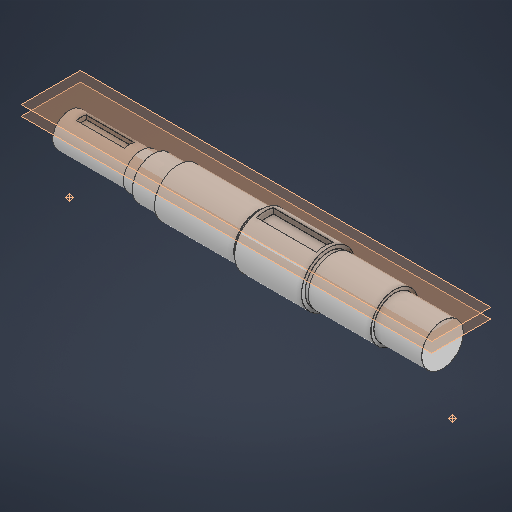
# Autodesk Inventor part: 1
Saved by Autodesk Inventor 2026 (Build 300175000, 175)
## iProperties
Created: 2026-08-23
Part Number: 1
Material: 常规
Document SubType Name: Modeling
Designer: 14170
Density: 1 g/cm^3
Appearance: 默认
Author: 14170
Autodesk Inventor part; units mm, degrees
ref_plane "YZ Plane" through (0, 0, 0) normal (1, 0, 0) x (0, 1, 0)
ref_plane "XY Plane" through (0, 0, 0) normal (0, 0, 1) x (1, 0, 0)
sketch "草图2" plane through (0, 0, 0) normal (0, 1, 0) x (1, 0, 0)
  line L0 (0, 0) -> (312, 0)
  line L1 (312, 0) -> (312, 17.5)
  line L2 (312, 17.5) -> (272, 17.5)
  line L3 (272, 17.5) -> (272, 20)
  line L4 (272, 20) -> (216.5, 20)
  line L5 (216.5, 20) -> (216.5, 22.5)
  line L6 (216.5, 22.5) -> (160.5, 22.5)
  line L7 (160.5, 22.5) -> (160.5, 20)
  line L8 (160.5, 20) -> (91, 20)
  line L9 (91, 20) -> (91, 17.5)
  line L10 (91, 17.5) -> (70, 17.5)
  line L11 (70, 17.5) -> (70, 15)
  line L12 (70, 15) -> (60, 15)
  line L13 (60, 15) -> (60, 14)
  line L14 (60, 14) -> (0, 14)
  line L15 (0, 14) -> (0, 0)
  constraints: 64 point on line, 32 end point
revolve "旋转1" add sketch "草图2" angle 360 about axis through (0, 0, 0) along (1, 0, 0)
ref_plane "工作平面1" through (0, 14, 0) normal (0, 1, 0) x (-1, 0, 0)
sketch "草图3" plane through (0, 14, 0) normal (0, 1, 0) x (1, 0, 0)
  line L0 (10, -4) -> (50, -4)
  line L1 (50, -4) -> (50, 4)
  line L2 (50, 4) -> (10, 4)
  line L3 (10, 4) -> (10, -4)
  constraints: 16 point on line, 8 end point, 2 parallel, 1 horizontal, 1 perpendicular
extrude "拉伸1" cut sketch "草图3" against normal blind 4
ref_plane "工作平面2" through (0, 22.5, 0) normal (0, 1, 0) x (-1, 0, 0)
sketch "草图4" plane through (0, 22.5, 0) normal (0, 1, 0) x (1, 0, 0)
  line L0 (163.5, -7) -> (213.5, -7)
  line L1 (213.5, -7) -> (213.5, 7)
  line L2 (213.5, 7) -> (163.5, 7)
  line L3 (163.5, 7) -> (163.5, -7)
  constraints: 8 end point, 8 point on line, 2 parallel, 1 horizontal, 1 perpendicular
extrude "拉伸2" cut sketch "草图4" against normal blind 5.5
sketch "草图5" plane through (0, 0, 0) normal (0, 1, 0) x (1, 0, 0)
  line L0 (150, 0) -> (230, 0)
  line L1 (157.5, 19.5) -> (160.5, 19.5)
  line L2 (160.5, 19.5) -> (160.5, 20)
  line L3 (160.5, 20) -> (157.5, 20)
  line L4 (157.5, 20) -> (157.5, 19.5)
  constraints: 16 point on line, 10 end point, 2 parallel, 1 horizontal, 1 perpendicular
revolve "旋转2" cut sketch "草图5" angle 360 about axis through (150, 0, 0) along (1, 0, 0)
sketch "草图6" plane through (0, 0, 0) normal (0, 1, 0) x (1, 0, 0)
  line L0 (210, 0) -> (230, 0)
  line L1 (216.5, 19.5) -> (219.5, 19.5)
  line L2 (219.5, 19.5) -> (219.5, 20)
  line L3 (219.5, 20) -> (216.5, 20)
  line L4 (216.5, 20) -> (216.5, 19.5)
  constraints: 16 point on line, 10 end point, 2 parallel, 1 horizontal, 1 perpendicular
revolve "旋转3" cut sketch "草图6" angle 360 about axis through (210, 0, 0) along (1, 0, 0)
sketch "草图12" plane through (0, 0, 0) normal (0, 0, 1) x (1, 0, 0)
  circle A0 centre (60, -35) radius 1
  line L0 (0, -50) -> (320, -50)
  constraints: 2 end point, 1 centre point
extrude "拉伸3" cut sketch "草图12" along normal blind 1
fillet "圆角1" radius 0.1 24 edges at (60, 0, 14) (50, 11.7082, 4) (30, 10, 4) (10, 11.7082, 4) (50, 10, 0) (50, 11.7082, -4) (10, 11.7082, -4) (30, 10, -4) (10, 10, 0) (70, 0, 15) (91, 0, 17.5) (157.5, 0, 19.5) (160.5, 0, 19.5) (216.5, 0, 19.5) (213.5, 19.1917, 7) (188.5, 17, 7) (163.5, 19.1917, 7) (213.5, 17, 0) (213.5, 19.1917, -7) (163.5, 19.1917, -7) (188.5, 17, -7) (163.5, 17, 0) (219.5, 0, 19.5) (272, 0, 17.5)
fillet "圆角1" radius 0.1 18 edges at (0, 0, 14) (30, 13.4164, 4) (50, 14, 0) (30, 13.4164, -4) (10, 14, 0) (60, 0, 15) (70, 0, 17.5) (91, 0, 20) (157.5, 0, 20) (160.5, 0, 22.5) (216.5, 0, 22.5) (188.5, 21.3834, 7) (213.5, 22.5, 0) (188.5, 21.3834, -7) (163.5, 22.5, 0) (219.5, 0, 20) (272, 0, 20) (312, 0, 17.5)
sketch "草图13" plane through (0, 0, 0) normal (0, 0, 1) x (1, 0, 0)
  line L0 (58.4, -36) -> (60, -36)
  line L1 (60, -36) -> (60, -34.4)
  arc A0 (58.4, -36) -> (60, -34.4) centre (58.4, -34.4) ccw
  constraints: 12 point on line, 8 point on circle, 4 end point, 1 centre point
revolve "旋转4" cut sketch "草图13" angle 360 about axis through (58.4, -36, 0) along (1, 0, 0)
